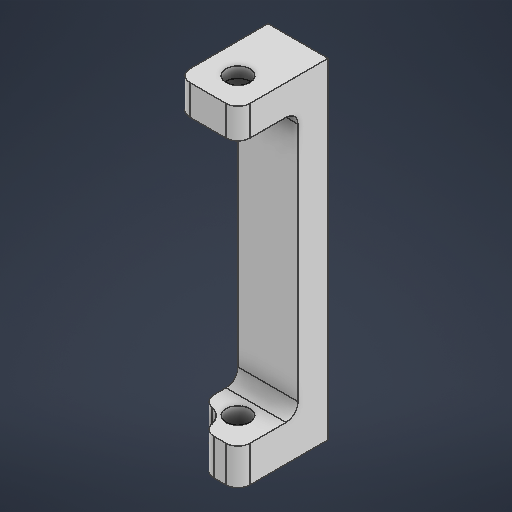
# Autodesk Inventor part: Pillar-tyB
Saved by Autodesk Inventor 2026.2 (Build 302298010, 298A)
## iProperties
Created: 2026-05-04
Part Number: Pillar-tyB
Material: 일반
Document SubType Name: Modeling
Designer: work
Density: 1 g/cm^3
Appearance: 기본값
Author: work
Autodesk Inventor part; units mm, degrees
ref_plane "YZ Plane" through (0, 0, 0) normal (1, 0, 0) x (0, 1, 0)
ref_plane "XZ Plane" through (0, 0, 0) normal (0, 1, 0) x (-1, 0, 0)
ref_plane "XY Plane" through (0, 0, 0) normal (0, 0, 1) x (1, 0, 0)
sketch "스케치1" plane through (0, 0, 0) normal (0, 1, 0) x (-1, 0, 0)
  circle A0 centre (0, 0) radius 2
  line L0 (-5, 5) -> (5, 5)
  line L1 (5, 5) -> (5, -5)
  line L2 (5, -5) -> (-5, -5)
  line L3 (-5, -5) -> (-5, 5)
  line L4 (-5, 5) -> (5, -5) construction
  line L5 (5, 5) -> (-5, -5) construction
  line L6 (5, -5) -> (-5, -5)
  line L7 (-5, -5) -> (-5, -11)
  line L8 (-5, -11) -> (5, -11)
  line L9 (5, -11) -> (5, -5)
  circle A1 centre (4, 4) radius 3.1
  point P0 (5, 1.0657)
  point P1 (1.0657, 5)
  dimension "d0" = 4
  dimension "d1" = 10
  dimension "d2" = 10
  dimension "d3" = 6
  dimension "d4" = 6.2
  dimension "d5" = 4
  dimension "d6" = 4
  constraints: 20 end point, 4 parallel, 2 centre point, 2 horizontal, 2 midpoint, 2 perpendicular, 1 coincident
  measures "d0" diameter of A0
  measures "d1" distance of L1.end L2.end
  measures "d2" distance of L0.end L1.end
  measures "d3" distance of L8.end L1.end
  measures "d4" diameter of A1
  measures "d5" horizontal distance of point (0, 0) A1.centre
  measures "d6" horizontal distance of A1.centre point (0, 0)
extrude "돌출1" add sketch "스케치1" along normal blind 6 contours L0 A1 L1 L2 L3
extrude "돌출2" add sketch "스케치1" along normal blind 50 contours L2 L9 L8 L7
sketch "스케치2" plane through (0, 50, 0) normal (0, 1, 0) x (1, 0, 0)
  line L0 (5, 5) -> (-5, 5) projected
  line L1 (-5, 5) -> (-5, -1.0657) projected
  arc A0 (-1.0657, -5) -> (-5, -1.0657) centre (-4, -4) ccw projected
  line L2 (-1.0657, -5) -> (5, -5) projected
  line L3 (5, -5) -> (5, 5) projected
  circle A1 centre (0, 0) radius 2 projected
  line L4 (-5, 5) -> (5, 5) projected
  line L5 (5, 5) -> (5, 11) projected
  line L6 (5, 11) -> (-5, 11) projected
  line L7 (-5, 11) -> (-5, 5) projected
  line L8 (-5, -1.0657) -> (-5, -5)
  line L9 (-5, -5) -> (-1.0657, -5)
  constraints: 4 end point, 1 perpendicular, 1 vertical
extrude "돌출3" add sketch "스케치2" along normal blind 5
sketch "스케치3" plane through (0, 50, 0) normal (0, -1, 0) x (1, 0, 0)
  circle A0 centre (0, 0) radius 2 projected
  constraints: 1 coincident
hole "구멍1" at (0, 50, 0) direction (0, 1, 0) diameter 4 end through all counterbore diameter 6.2 counterbore depth 3.2
fillet "모깎기1" radius 2 7 edges at (0, 6, -5) (0, 50, -5) (-5, 52.5, 5) (5, 52.5, 5) (-5, 3, 1.0657) (-1.0657, 3, 5) (5, 3, 5)
chamfer "모따기1" distance 1 angle 45 4 edges at (-5, 27.5, -11) (5, 27.5, -11) (0, 55, -11) (0, 0, -11)
